Autodesk Fusion 360 part; units mm, degrees
(part 5 of 8)
sketch "D output shaft | protrusion from mounting face | profile (4)" plane through (0, 0, 2) normal (0, 0, 1) x (1, 0, 0) in component "J4 | NEMA17 drawing reference"
  line L0 (-2.5, 0) -> (-2.4786, -0.3263)
  line L1 (-2.4786, -0.3263) -> (-2.4148, -0.647)
  line L2 (-2.4148, -0.647) -> (-2.3097, -0.9567)
  line L3 (-2.3097, -0.9567) -> (-2.1651, -1.25)
  line L4 (-2.1651, -1.25) -> (-1.9834, -1.5219)
  line L5 (-1.9834, -1.5219) -> (-1.7678, -1.7678)
  line L6 (-1.7678, -1.7678) -> (-1.5219, -1.9834)
  line L7 (-1.5219, -1.9834) -> (-1.25, -2.1651)
  line L8 (-1.25, -2.1651) -> (-0.9567, -2.3097)
  line L9 (-0.9567, -2.3097) -> (-0.647, -2.4148)
  line L10 (-0.647, -2.4148) -> (-0.3263, -2.4786)
  line L11 (-0.3263, -2.4786) -> (0, -2.5)
  line L12 (0, -2.5) -> (0.3263, -2.4786)
  line L13 (0.3263, -2.4786) -> (0.647, -2.4148)
  line L14 (0.647, -2.4148) -> (0.9567, -2.3097)
  line L15 (0.9567, -2.3097) -> (1.25, -2.1651)
  line L16 (1.25, -2.1651) -> (1.5219, -1.9834)
  line L17 (1.5219, -1.9834) -> (1.7678, -1.7678)
  line L18 (1.7678, -1.7678) -> (1.9834, -1.5219)
  line L19 (1.9834, -1.5219) -> (2, -1.25)
  line L20 (2, -1.25) -> (2, 1.25)
  line L21 (2, 1.25) -> (1.9834, 1.5219)
  line L22 (1.9834, 1.5219) -> (1.7678, 1.7678)
  line L23 (1.7678, 1.7678) -> (1.5219, 1.9834)
  line L24 (1.5219, 1.9834) -> (1.25, 2.1651)
  line L25 (1.25, 2.1651) -> (0.9567, 2.3097)
  line L26 (0.9567, 2.3097) -> (0.647, 2.4148)
  line L27 (0.647, 2.4148) -> (0.3263, 2.4786)
  line L28 (0.3263, 2.4786) -> (0, 2.5)
  line L29 (0, 2.5) -> (-0.3263, 2.4786)
  line L30 (-0.3263, 2.4786) -> (-0.647, 2.4148)
  line L31 (-0.647, 2.4148) -> (-0.9567, 2.3097)
  line L32 (-0.9567, 2.3097) -> (-1.25, 2.1651)
  line L33 (-1.25, 2.1651) -> (-1.5219, 1.9834)
  line L34 (-1.5219, 1.9834) -> (-1.7678, 1.7678)
  line L35 (-1.7678, 1.7678) -> (-1.9834, 1.5219)
  line L36 (-1.9834, 1.5219) -> (-2.1651, 1.25)
  line L37 (-2.1651, 1.25) -> (-2.3097, 0.9567)
  line L38 (-2.3097, 0.9567) -> (-2.4148, 0.647)
  line L39 (-2.4148, 0.647) -> (-2.4786, 0.3263)
  line L40 (-2.4786, 0.3263) -> (-2.5, 0)
extrude "D output shaft | protrusion from mounting face'''" add sketch "D output shaft | protrusion from mounting face | profile (4)" along normal blind 21 separate body makes body 193 in component "J4 | NEMA17 drawing reference"
ref_plane "WorkPlane5" through (0, 0, -39) normal (0, 0, 1) x (1, 0, 0) in component "J4 | NEMA17 drawing reference"
sketch "Cable connector | profile (4)" plane through (0, 0, -39) normal (0, 0, 1) x (1, 0, 0) in component "J4 | NEMA17 drawing reference"
  line L0 (-5.2, -24.65) -> (5.2, -24.65)
  line L1 (5.2, -24.65) -> (6, -23.85)
  line L2 (6, -23.85) -> (6, -20.45)
  line L3 (6, -20.45) -> (5.2, -19.65)
  line L4 (5.2, -19.65) -> (-5.2, -19.65)
  line L5 (-5.2, -19.65) -> (-6, -20.45)
  line L6 (-6, -20.45) -> (-6, -23.85)
  line L7 (-6, -23.85) -> (-5.2, -24.65)
extrude "Cable connector'''" add sketch "Cable connector | profile (4)" along normal blind 8 separate body makes body 194 in component "J4 | NEMA17 drawing reference"
sketch "MG996R case | 40.7 x 19.7 x 37 nominal | profile" plane through (0, 0, 0) normal (0, 0, 1) x (1, 0, 0) in component "MG996R Robot 180 | drawing reconstruction, fit pending"
  line L0 (-19.35, -9.85) -> (19.35, -9.85)
  line L1 (19.35, -9.85) -> (20.35, -8.85)
  line L2 (20.35, -8.85) -> (20.35, 8.85)
  line L3 (20.35, 8.85) -> (19.35, 9.85)
  line L4 (19.35, 9.85) -> (-19.35, 9.85)
  line L5 (-19.35, 9.85) -> (-20.35, 8.85)
  line L6 (-20.35, 8.85) -> (-20.35, -8.85)
  line L7 (-20.35, -8.85) -> (-19.35, -9.85)
extrude "MG996R case | 40.7 x 19.7 x 37 nominal" add sketch "MG996R case | 40.7 x 19.7 x 37 nominal | profile" along normal blind 32 separate body makes body 195 in component "MG996R Robot 180 | drawing reconstruction, fit pending"
ref_plane "WorkPlane1" through (0, 0, 32) normal (0, 0, 1) x (1, 0, 0) in component "MG996R Robot 180 | drawing reconstruction, fit pending"
sketch "MG996R top cover | profile" plane through (0, 0, 32) normal (0, 0, 1) x (1, 0, 0) in component "MG996R Robot 180 | drawing reconstruction, fit pending"
  line L0 (-19.35, -9.85) -> (19.35, -9.85)
  line L1 (19.35, -9.85) -> (20.35, -8.85)
  line L2 (20.35, -8.85) -> (20.35, 8.85)
  line L3 (20.35, 8.85) -> (19.35, 9.85)
  line L4 (19.35, 9.85) -> (-19.35, 9.85)
  line L5 (-19.35, 9.85) -> (-20.35, 8.85)
  line L6 (-20.35, 8.85) -> (-20.35, -8.85)
  line L7 (-20.35, -8.85) -> (-19.35, -9.85)
extrude "MG996R top cover" add sketch "MG996R top cover | profile" along normal blind 5 separate body makes body 196 in component "MG996R Robot 180 | drawing reconstruction, fit pending"
ref_plane "WorkPlane2" through (0, 0, 37) normal (0, 0, 1) x (1, 0, 0) in component "MG996R Robot 180 | drawing reconstruction, fit pending"
sketch "MG996R boss | offset is provisional | profile" plane through (0, 0, 37) normal (0, 0, 1) x (1, 0, 0) in component "MG996R Robot 180 | drawing reconstruction, fit pending"
  circle A0 centre (10.35, 0) radius 6.5
extrude "MG996R boss | offset is provisional" add sketch "MG996R boss | offset is provisional | profile" along normal blind 2.5 separate body makes body 197 in component "MG996R Robot 180 | drawing reconstruction, fit pending"
ref_plane "WorkPlane3" through (0, 0, 39.5) normal (0, 0, 1) x (1, 0, 0) in component "MG996R Robot 180 | drawing reconstruction, fit pending"
sketch "MG996R spline envelope | purchased fit pending | profile" plane through (0, 0, 39.5) normal (0, 0, 1) x (1, 0, 0) in component "MG996R Robot 180 | drawing reconstruction, fit pending"
  circle A0 centre (10.35, 0) radius 3
extrude "MG996R spline envelope | purchased fit pending" add sketch "MG996R spline envelope | purchased fit pending | profile" along normal blind 3.4 separate body makes body 198 in component "MG996R Robot 180 | drawing reconstruction, fit pending"
ref_plane "WorkPlane4" through (0, 0, 26.8) normal (0, 0, 1) x (1, 0, 0) in component "MG996R Robot 180 | drawing reconstruction, fit pending"
sketch "MG996R nominal ear | verify hole pattern | profile" plane through (0, 0, 26.8) normal (0, 0, 1) x (1, 0, 0) in component "MG996R Robot 180 | drawing reconstruction, fit pending"
  line L0 (-26.4, -10) -> (-20.95, -10)
  line L1 (-20.95, -10) -> (-20.35, -9.4)
  line L2 (-20.35, -9.4) -> (-20.35, 9.4)
  line L3 (-20.35, 9.4) -> (-20.95, 10)
  line L4 (-20.95, 10) -> (-26.4, 10)
  line L5 (-26.4, 10) -> (-27, 9.4)
  line L6 (-27, 9.4) -> (-27, -9.4)
  line L7 (-27, -9.4) -> (-26.4, -10)
  circle A0 centre (-24.25, -5) radius 1.25
  circle A1 centre (-24.25, 5) radius 1.25
extrude "MG996R nominal ear | verify hole pattern" add sketch "MG996R nominal ear | verify hole pattern | profile" along normal blind 2.5 separate body makes body 199 in component "MG996R Robot 180 | drawing reconstruction, fit pending"
ref_plane "WorkPlane5" through (0, 0, 26.8) normal (0, 0, 1) x (1, 0, 0) in component "MG996R Robot 180 | drawing reconstruction, fit pending"
sketch "MG996R nominal ear | verify hole pattern | profile (1)" plane through (0, 0, 26.8) normal (0, 0, 1) x (1, 0, 0) in component "MG996R Robot 180 | drawing reconstruction, fit pending"
  line L0 (20.95, -10) -> (26.4, -10)
  line L1 (26.4, -10) -> (27, -9.4)
  line L2 (27, -9.4) -> (27, 9.4)
  line L3 (27, 9.4) -> (26.4, 10)
  line L4 (26.4, 10) -> (20.95, 10)
  line L5 (20.95, 10) -> (20.35, 9.4)
  line L6 (20.35, 9.4) -> (20.35, -9.4)
  line L7 (20.35, -9.4) -> (20.95, -10)
  circle A0 centre (24.25, -5) radius 1.25
  circle A1 centre (24.25, 5) radius 1.25
extrude "MG996R nominal ear | verify hole pattern (1)" add sketch "MG996R nominal ear | verify hole pattern | profile (1)" along normal blind 2.5 separate body makes body 200 in component "MG996R Robot 180 | drawing reconstruction, fit pending"
ref_plane "WorkPlane6" through (0, 0, 36.8) normal (0, 0, 1) x (1, 0, 0) in component "MG996R Robot 180 | drawing reconstruction, fit pending"
sketch "MG996R case screw | profile" plane through (0, 0, 36.8) normal (0, 0, 1) x (1, 0, 0) in component "MG996R Robot 180 | drawing reconstruction, fit pending"
  line L0 (-15.8742, -5.35) -> (-17, -4.7)
  line L1 (-17, -4.7) -> (-18.1258, -5.35)
  line L2 (-18.1258, -5.35) -> (-18.1258, -6.65)
  line L3 (-18.1258, -6.65) -> (-17, -7.3)
  line L4 (-17, -7.3) -> (-15.8742, -6.65)
  line L5 (-15.8742, -6.65) -> (-15.8742, -5.35)
  circle A0 centre (-17, -6) radius 0.9
extrude "MG996R case screw" add sketch "MG996R case screw | profile" along normal blind 1 separate body makes body 201 in component "MG996R Robot 180 | drawing reconstruction, fit pending"
ref_plane "WorkPlane7" through (0, 0, 36.8) normal (0, 0, 1) x (1, 0, 0) in component "MG996R Robot 180 | drawing reconstruction, fit pending"
sketch "MG996R case screw | profile (1)" plane through (0, 0, 36.8) normal (0, 0, 1) x (1, 0, 0) in component "MG996R Robot 180 | drawing reconstruction, fit pending"
  line L0 (-15.8742, 6.65) -> (-17, 7.3)
  line L1 (-17, 7.3) -> (-18.1258, 6.65)
  line L2 (-18.1258, 6.65) -> (-18.1258, 5.35)
  line L3 (-18.1258, 5.35) -> (-17, 4.7)
  line L4 (-17, 4.7) -> (-15.8742, 5.35)
  line L5 (-15.8742, 5.35) -> (-15.8742, 6.65)
  circle A0 centre (-17, 6) radius 0.9
extrude "MG996R case screw (1)" add sketch "MG996R case screw | profile (1)" along normal blind 1 separate body makes body 202 in component "MG996R Robot 180 | drawing reconstruction, fit pending"
ref_plane "WorkPlane8" through (0, 0, 36.8) normal (0, 0, 1) x (1, 0, 0) in component "MG996R Robot 180 | drawing reconstruction, fit pending"
sketch "MG996R case screw | profile (2)" plane through (0, 0, 36.8) normal (0, 0, 1) x (1, 0, 0) in component "MG996R Robot 180 | drawing reconstruction, fit pending"
  line L0 (18.1258, -5.35) -> (17, -4.7)
  line L1 (17, -4.7) -> (15.8742, -5.35)
  line L2 (15.8742, -5.35) -> (15.8742, -6.65)
  line L3 (15.8742, -6.65) -> (17, -7.3)
  line L4 (17, -7.3) -> (18.1258, -6.65)
  line L5 (18.1258, -6.65) -> (18.1258, -5.35)
  circle A0 centre (17, -6) radius 0.9
extrude "MG996R case screw (2)" add sketch "MG996R case screw | profile (2)" along normal blind 1 separate body makes body 203 in component "MG996R Robot 180 | drawing reconstruction, fit pending"
ref_plane "WorkPlane9" through (0, 0, 36.8) normal (0, 0, 1) x (1, 0, 0) in component "MG996R Robot 180 | drawing reconstruction, fit pending"
sketch "MG996R case screw | profile (3)" plane through (0, 0, 36.8) normal (0, 0, 1) x (1, 0, 0) in component "MG996R Robot 180 | drawing reconstruction, fit pending"
  line L0 (18.1258, 6.65) -> (17, 7.3)
  line L1 (17, 7.3) -> (15.8742, 6.65)
  line L2 (15.8742, 6.65) -> (15.8742, 5.35)
  line L3 (15.8742, 5.35) -> (17, 4.7)
  line L4 (17, 4.7) -> (18.1258, 5.35)
  line L5 (18.1258, 5.35) -> (18.1258, 6.65)
  circle A0 centre (17, 6) radius 0.9
extrude "MG996R case screw (3)" add sketch "MG996R case screw | profile (3)" along normal blind 1 separate body makes body 204 in component "MG996R Robot 180 | drawing reconstruction, fit pending"
ref_plane "WorkPlane1" through (0, 0, -14) normal (0, 0, 1) x (1, 0, 0) in component "11:1 twin-disc shoulder | original geometry"
sketch "Fixed ring | 12 roller stations | profile" plane through (0, 0, -14) normal (0, 0, 1) x (1, 0, 0) in component "11:1 twin-disc shoulder | original geometry"
  circle A0 centre (0, 0) radius 49
  circle A1 centre (0, 0) radius 45.4
extrude "Fixed ring | 12 roller stations" add sketch "Fixed ring | 12 roller stations | profile" along normal blind 28 separate body makes body 205 in component "11:1 twin-disc shoulder | original geometry"
ref_plane "WorkPlane2" through (0, 0, -17) normal (0, 0, 1) x (1, 0, 0) in component "11:1 twin-disc shoulder | original geometry"
sketch "Rear roller support | profile" plane through (0, 0, -17) normal (0, 0, 1) x (1, 0, 0) in component "11:1 twin-disc shoulder | original geometry"
  line L0 (49, 0) -> (48.7641, 4.8028)
  line L1 (48.7641, 4.8028) -> (48.0585, 9.5594)
  line L2 (48.0585, 9.5594) -> (46.8901, 14.2239)
  line L3 (46.8901, 14.2239) -> (45.2701, 18.7515)
  line L4 (45.2701, 18.7515) -> (43.2141, 23.0984)
  line L5 (43.2141, 23.0984) -> (40.742, 27.2229)
  line L6 (40.742, 27.2229) -> (37.8775, 31.0853)
  line L7 (37.8775, 31.0853) -> (34.6482, 34.6482)
  line L8 (34.6482, 34.6482) -> (31.0853, 37.8775)
  line L9 (31.0853, 37.8775) -> (27.2229, 40.742)
  line L10 (27.2229, 40.742) -> (23.0984, 43.2141)
  line L11 (23.0984, 43.2141) -> (18.7515, 45.2701)
  line L12 (18.7515, 45.2701) -> (14.2239, 46.8901)
  line L13 (14.2239, 46.8901) -> (9.5594, 48.0585)
  line L14 (9.5594, 48.0585) -> (4.8028, 48.7641)
  line L15 (4.8028, 48.7641) -> (0, 49)
  line L16 (0, 49) -> (-4.8028, 48.7641)
  line L17 (-4.8028, 48.7641) -> (-9.5594, 48.0585)
  line L18 (-9.5594, 48.0585) -> (-14.2239, 46.8901)
  line L19 (-14.2239, 46.8901) -> (-18.7515, 45.2701)
  line L20 (-18.7515, 45.2701) -> (-23.0984, 43.2141)
  line L21 (-23.0984, 43.2141) -> (-27.2229, 40.742)
  line L22 (-27.2229, 40.742) -> (-31.0853, 37.8775)
  line L23 (-31.0853, 37.8775) -> (-34.6482, 34.6482)
  line L24 (-34.6482, 34.6482) -> (-37.8775, 31.0853)
  line L25 (-37.8775, 31.0853) -> (-40.742, 27.2229)
  line L26 (-40.742, 27.2229) -> (-43.2141, 23.0984)
  line L27 (-43.2141, 23.0984) -> (-45.2701, 18.7515)
  line L28 (-45.2701, 18.7515) -> (-46.8901, 14.2239)
  line L29 (-46.8901, 14.2239) -> (-48.0585, 9.5594)
  line L30 (-48.0585, 9.5594) -> (-48.7641, 4.8028)
  line L31 (-48.7641, 4.8028) -> (-49, 0)
  line L32 (-49, 0) -> (-48.7641, -4.8028)
  line L33 (-48.7641, -4.8028) -> (-48.0585, -9.5594)
  line L34 (-48.0585, -9.5594) -> (-46.8901, -14.2239)
  line L35 (-46.8901, -14.2239) -> (-45.2701, -18.7515)
  line L36 (-45.2701, -18.7515) -> (-43.2141, -23.0984)
  line L37 (-43.2141, -23.0984) -> (-40.742, -27.2229)
  line L38 (-40.742, -27.2229) -> (-37.8775, -31.0853)
  line L39 (-37.8775, -31.0853) -> (-34.6482, -34.6482)
  line L40 (-34.6482, -34.6482) -> (-31.0853, -37.8775)
  line L41 (-31.0853, -37.8775) -> (-27.2229, -40.742)
  line L42 (-27.2229, -40.742) -> (-23.0984, -43.2141)
  line L43 (-23.0984, -43.2141) -> (-18.7515, -45.2701)
  line L44 (-18.7515, -45.2701) -> (-14.2239, -46.8901)
  line L45 (-14.2239, -46.8901) -> (-9.5594, -48.0585)
  line L46 (-9.5594, -48.0585) -> (-4.8028, -48.7641)
  line L47 (-4.8028, -48.7641) -> (0, -49)
  line L48 (0, -49) -> (4.8028, -48.7641)
  line L49 (4.8028, -48.7641) -> (9.5594, -48.0585)
  line L50 (9.5594, -48.0585) -> (14.2239, -46.8901)
  line L51 (14.2239, -46.8901) -> (18.7515, -45.2701)
  line L52 (18.7515, -45.2701) -> (23.0984, -43.2141)
  line L53 (23.0984, -43.2141) -> (27.2229, -40.742)
  line L54 (27.2229, -40.742) -> (31.0853, -37.8775)
  line L55 (31.0853, -37.8775) -> (34.6482, -34.6482)
  line L56 (34.6482, -34.6482) -> (37.8775, -31.0853)
  line L57 (37.8775, -31.0853) -> (40.742, -27.2229)
  line L58 (40.742, -27.2229) -> (43.2141, -23.0984)
  line L59 (43.2141, -23.0984) -> (45.2701, -18.7515)
  line L60 (45.2701, -18.7515) -> (46.8901, -14.2239)
  line L61 (46.8901, -14.2239) -> (48.0585, -9.5594)
  line L62 (48.0585, -9.5594) -> (48.7641, -4.8028)
  line L63 (48.7641, -4.8028) -> (49, 0)
  circle A0 centre (0, 0) radius 21.1
  circle A1 centre (47, 0) radius 1.6
  circle A2 centre (23.5, 40.7032) radius 1.6
  circle A3 centre (-23.5, 40.7032) radius 1.6
  circle A4 centre (-47, 0) radius 1.6
  circle A5 centre (-23.5, -40.7032) radius 1.6
  circle A6 centre (23.5, -40.7032) radius 1.6
extrude "Rear roller support" add sketch "Rear roller support | profile" along normal blind 3 separate body makes body 206 in component "11:1 twin-disc shoulder | original geometry"
ref_plane "WorkPlane3" through (0, 0, 14) normal (0, 0, 1) x (1, 0, 0) in component "11:1 twin-disc shoulder | original geometry"
sketch "Front roller support | profile" plane through (0, 0, 14) normal (0, 0, 1) x (1, 0, 0) in component "11:1 twin-disc shoulder | original geometry"
  line L0 (49, 0) -> (48.7641, 4.8028)
  line L1 (48.7641, 4.8028) -> (48.0585, 9.5594)
  line L2 (48.0585, 9.5594) -> (46.8901, 14.2239)
  line L3 (46.8901, 14.2239) -> (45.2701, 18.7515)
  line L4 (45.2701, 18.7515) -> (43.2141, 23.0984)
  line L5 (43.2141, 23.0984) -> (40.742, 27.2229)
  line L6 (40.742, 27.2229) -> (37.8775, 31.0853)
  line L7 (37.8775, 31.0853) -> (34.6482, 34.6482)
  line L8 (34.6482, 34.6482) -> (31.0853, 37.8775)
  line L9 (31.0853, 37.8775) -> (27.2229, 40.742)
  line L10 (27.2229, 40.742) -> (23.0984, 43.2141)
  line L11 (23.0984, 43.2141) -> (18.7515, 45.2701)
  line L12 (18.7515, 45.2701) -> (14.2239, 46.8901)
  line L13 (14.2239, 46.8901) -> (9.5594, 48.0585)
  line L14 (9.5594, 48.0585) -> (4.8028, 48.7641)
  line L15 (4.8028, 48.7641) -> (0, 49)
  line L16 (0, 49) -> (-4.8028, 48.7641)
  line L17 (-4.8028, 48.7641) -> (-9.5594, 48.0585)
  line L18 (-9.5594, 48.0585) -> (-14.2239, 46.8901)
  line L19 (-14.2239, 46.8901) -> (-18.7515, 45.2701)
  line L20 (-18.7515, 45.2701) -> (-23.0984, 43.2141)
  line L21 (-23.0984, 43.2141) -> (-27.2229, 40.742)
  line L22 (-27.2229, 40.742) -> (-31.0853, 37.8775)
  line L23 (-31.0853, 37.8775) -> (-34.6482, 34.6482)
  line L24 (-34.6482, 34.6482) -> (-37.8775, 31.0853)
  line L25 (-37.8775, 31.0853) -> (-40.742, 27.2229)
  line L26 (-40.742, 27.2229) -> (-43.2141, 23.0984)
  line L27 (-43.2141, 23.0984) -> (-45.2701, 18.7515)
  line L28 (-45.2701, 18.7515) -> (-46.8901, 14.2239)
  line L29 (-46.8901, 14.2239) -> (-48.0585, 9.5594)
  line L30 (-48.0585, 9.5594) -> (-48.7641, 4.8028)
  line L31 (-48.7641, 4.8028) -> (-49, 0)
  line L32 (-49, 0) -> (-48.7641, -4.8028)
  line L33 (-48.7641, -4.8028) -> (-48.0585, -9.5594)
  line L34 (-48.0585, -9.5594) -> (-46.8901, -14.2239)
  line L35 (-46.8901, -14.2239) -> (-45.2701, -18.7515)
  line L36 (-45.2701, -18.7515) -> (-43.2141, -23.0984)
  line L37 (-43.2141, -23.0984) -> (-40.742, -27.2229)
  line L38 (-40.742, -27.2229) -> (-37.8775, -31.0853)
  line L39 (-37.8775, -31.0853) -> (-34.6482, -34.6482)
  line L40 (-34.6482, -34.6482) -> (-31.0853, -37.8775)
  line L41 (-31.0853, -37.8775) -> (-27.2229, -40.742)
  line L42 (-27.2229, -40.742) -> (-23.0984, -43.2141)
  line L43 (-23.0984, -43.2141) -> (-18.7515, -45.2701)
  line L44 (-18.7515, -45.2701) -> (-14.2239, -46.8901)
  line L45 (-14.2239, -46.8901) -> (-9.5594, -48.0585)
  line L46 (-9.5594, -48.0585) -> (-4.8028, -48.7641)
  line L47 (-4.8028, -48.7641) -> (0, -49)
  line L48 (0, -49) -> (4.8028, -48.7641)
  line L49 (4.8028, -48.7641) -> (9.5594, -48.0585)
  line L50 (9.5594, -48.0585) -> (14.2239, -46.8901)
  line L51 (14.2239, -46.8901) -> (18.7515, -45.2701)
  line L52 (18.7515, -45.2701) -> (23.0984, -43.2141)
  line L53 (23.0984, -43.2141) -> (27.2229, -40.742)
  line L54 (27.2229, -40.742) -> (31.0853, -37.8775)
  line L55 (31.0853, -37.8775) -> (34.6482, -34.6482)
  line L56 (34.6482, -34.6482) -> (37.8775, -31.0853)
  line L57 (37.8775, -31.0853) -> (40.742, -27.2229)
  line L58 (40.742, -27.2229) -> (43.2141, -23.0984)
  line L59 (43.2141, -23.0984) -> (45.2701, -18.7515)
  line L60 (45.2701, -18.7515) -> (46.8901, -14.2239)
  line L61 (46.8901, -14.2239) -> (48.0585, -9.5594)
  line L62 (48.0585, -9.5594) -> (48.7641, -4.8028)
  line L63 (48.7641, -4.8028) -> (49, 0)
  circle A0 centre (0, 0) radius 21.1
  circle A1 centre (47, 0) radius 1.6
  circle A2 centre (23.5, 40.7032) radius 1.6
  circle A3 centre (-23.5, 40.7032) radius 1.6
  circle A4 centre (-47, 0) radius 1.6
  circle A5 centre (-23.5, -40.7032) radius 1.6
  circle A6 centre (23.5, -40.7032) radius 1.6
extrude "Front roller support" add sketch "Front roller support | profile" along normal blind 3 separate body makes body 207 in component "11:1 twin-disc shoulder | original geometry"
ref_plane "WorkPlane4" through (0, 0, -6) normal (0, 0, 1) x (1, 0, 0) in component "11:1 twin-disc shoulder | original geometry"
sketch "Cycloidal disc A | 11 lobes | profile" plane through (0, 0, -6) normal (0, 0, 1) x (1, 0, 0) in component "11:1 twin-disc shoulder | original geometry"
  spline S0 degree 3 poles (34.9, 0) (34.9, 0.4967) (35.0026, 1.49) (35.3283, 2.6754) (35.659, 3.5694) (35.9489, 4.2967) (36.1986, 4.9569) (36.4118, 5.6126) (36.5843, 6.2979) (36.7055, 7.0274) (36.7619, 7.8014) (36.7413, 8.61) (36.635, 9.4363) (36.4398, 10.2593) (36.159, 11.0571) (35.8018, 11.8097) (35.382, 12.501) (34.916, 13.1217) (34.4197, 13.6699) (33.9041, 14.1531) (33.3703, 14.5895) (32.8032, 15.0099) (32.1662, 15.465) (31.4046, 16.0383) (30.4898, 16.8594) (29.5547, 18.0297) (28.8787, 19.3664) (28.5118, 20.5396) (28.3067, 21.4705) (28.1573, 22.2391) (28.0104, 22.9295) (27.8353, 23.5964) (27.6099, 24.2662) (27.3174, 24.9453) (26.9464, 25.627) (26.4919, 26.2961) (25.9558, 26.9337) (25.3467, 27.5205) (24.6791, 28.0399) (23.9717, 28.4799) (23.2448, 28.8345) (22.5172, 29.1047) (21.8033, 29.2975) (21.1083, 29.4253) (20.4233, 29.5038) (19.719, 29.5509) (18.937, 29.5894) (17.9864, 29.6599) (16.7728, 29.8561) (15.3535, 30.335) (14.0622, 31.094) (13.1192, 31.8827) (12.4433, 32.5549) (11.9022, 33.1207) (11.4054, 33.6222) (10.8975, 34.0885) (10.3457, 34.5301) (9.7325, 34.9433) (9.0519, 35.3162) (8.3078, 35.6333) (7.5121, 35.8798) (6.6824, 36.0442) (5.84, 36.1203) (5.007, 36.1079) (4.2037, 36.0133) (3.4456, 35.8472) (2.7408, 35.6235) (2.087, 35.3552) (1.4683, 35.0509) (0.8503, 34.7098) (0.1717, 34.3193) (-0.6661, 33.8647) (-1.7931, 33.3737) (-3.246, 33.0092) (-4.7428, 32.9496) (-5.9624, 33.1032) (-6.8944, 33.3034) (-7.6555, 33.4868) (-8.3446, 33.64) (-9.0239, 33.7577) (-9.7268, 33.8309) (-10.4662, 33.847) (-11.2403, 33.7927) (-12.0377, 33.6573) (-12.8404, 33.4344) (-13.6273, 33.1241) (-14.3771, 32.7327) (-15.0711, 32.272) (-15.6957, 31.758) (-16.2437, 31.2085) (-16.7157, 30.6392) (-17.1206, 30.0601) (-17.4766, 29.4696) (-17.812, 28.8485) (-18.1718, 28.1531) (-18.6309, 27.3177) (-19.3135, 26.2954) (-20.3387, 25.2032) (-21.5656, 24.3439) (-22.6747, 23.8137) (-23.567, 23.4782) (-24.3064, 23.221) (-24.969, 22.9774) (-25.6041, 22.7091) (-26.235, 22.3907) (-26.8656, 22.0045) (-27.4876, 21.5403) (-28.0852, 20.9952) (-28.64, 20.3738) (-29.1341, 19.6874) (-29.5532, 18.9527) (-29.888, 18.1899) (-30.1356, 17.4198) (-30.2995, 16.6613) (-30.3888, 15.9272) (-30.4164, 15.221) (-30.3966, 14.5319) (-30.343, 13.828) (-30.2697, 13.0485) (-30.2043, 12.0975) (-30.2258, 10.8684) (-30.4978, 9.3954) (-31.0653, 8.0091) (-31.7117, 6.9635) (-32.281, 6.1989) (-32.764, 5.5828) (-33.1896, 5.0196) (-33.5789, 4.4505) (-33.9375, 3.8416) (-34.2592, 3.1758) (-34.5315, 2.449) (-34.7395, 1.6674) (-34.8702, 0.8446) (-34.9149, 0) (-34.8702, -0.8446) (-34.7395, -1.6674) (-34.5315, -2.449) (-34.2592, -3.1758) (-33.9375, -3.8416) (-33.5789, -4.4505) (-33.1896, -5.0196) (-32.764, -5.5828) (-32.281, -6.1989) (-31.7117, -6.9635) (-31.0653, -8.0091) (-30.4978, -9.3954) (-30.2258, -10.8684) (-30.2043, -12.0975) (-30.2697, -13.0485) (-30.343, -13.828) (-30.3966, -14.5319) (-30.4164, -15.221) (-30.3888, -15.9272) (-30.2995, -16.6613) (-30.1356, -17.4198) (-29.888, -18.1899) (-29.5532, -18.9527) (-29.1341, -19.6874) (-28.64, -20.3738) (-28.0852, -20.9952) (-27.4876, -21.5403) (-26.8656, -22.0045) (-26.235, -22.3907) (-25.6041, -22.7091) (-24.969, -22.9774) (-24.3064, -23.221) (-23.567, -23.4782) (-22.6747, -23.8137) (-21.5656, -24.3439) (-20.3387, -25.2032) (-19.3135, -26.2954) (-18.6309, -27.3177) (-18.1718, -28.1531) (-17.812, -28.8485) (-17.4766, -29.4696) (-17.1206, -30.0601) (-16.7157, -30.6392) (-16.2437, -31.2085) (-15.6957, -31.758) (-15.0711, -32.272) (-14.3771, -32.7327) (-13.6273, -33.1241) (-12.8404, -33.4344) (-12.0377, -33.6573) (-11.2403, -33.7927) (-10.4662, -33.847) (-9.7268, -33.8309) (-9.0239, -33.7577) (-8.3446, -33.64) (-7.6555, -33.4868) (-6.8944, -33.3034) (-5.9624, -33.1032) (-4.7428, -32.9496) (-3.246, -33.0092) (-1.7931, -33.3737) (-0.6661, -33.8647) (0.1717, -34.3193) (0.8503, -34.7098) (1.4683, -35.0509) (2.087, -35.3552) (2.7408, -35.6235) (3.4456, -35.8472) (4.2037, -36.0133) (5.007, -36.1079) (5.84, -36.1203) (6.6824, -36.0442) (7.5121, -35.8798) (8.3078, -35.6333) (9.0519, -35.3162) (9.7325, -34.9433) (10.3457, -34.5301) (10.8975, -34.0885) (11.4054, -33.6222) (11.9022, -33.1207) (12.4433, -32.5549) (13.1192, -31.8827) (14.0622, -31.094) (15.3535, -30.335) (16.7728, -29.8561) (17.9864, -29.6599) (18.937, -29.5894) (19.719, -29.5509) (20.4233, -29.5038) (21.1083, -29.4253) (21.8033, -29.2975) (22.5172, -29.1047) (23.2448, -28.8345) (23.9717, -28.4799) (24.6791, -28.0399) (25.3467, -27.5205) (25.9558, -26.9337) (26.4919, -26.2961) (26.9464, -25.627) (27.3174, -24.9453) (27.6099, -24.2662) (27.8353, -23.5964) (28.0104, -22.9295) (28.1573, -22.2391) (28.3067, -21.4705) (28.5118, -20.5396) (28.8787, -19.3664) (29.5547, -18.0297) (30.4898, -16.8594) (31.4046, -16.0383) (32.1662, -15.465) (32.8032, -15.0099) (33.3703, -14.5895) (33.9041, -14.1531) (34.4197, -13.6699) (34.916, -13.1217) (35.382, -12.501) (35.8018, -11.8097) (36.159, -11.0571) (36.4398, -10.2593) (36.635, -9.4363) (36.7413, -8.61) (36.7619, -7.8014) (36.7055, -7.0274) (36.5843, -6.2979) (36.4118, -5.6126) (36.1986, -4.9569) (35.9489, -4.2967) (35.659, -3.5694) (35.3283, -2.6754) (35.0026, -1.49) (34.9, -0.4967) (34.9, 0) knots 3 3 3 3 4 5 6 7 8 9 10 11 12 13 14 15 16 17 18 19 20 21 22 23 24 25 26 27 28 29 30 31 32 33 34 35 36 37 38 39 40 41 42 43 44 45 46 47 48 49 50 51 52 53 54 55 56 57 58 59 60 61 62 63 64 65 66 67 68 69 70 71 72 73 74 75 76 77 78 79 80 81 82 83 84 85 86 87 88 89 90 91 92 93 94 95 96 97 98 99 100 101 102 103 104 105 106 107 108 109 110 111 112 113 114 115 116 117 118 119 120 121 122 123 124 125 126 127 128 129 130 131 132 133 134 135 136 137 138 139 140 141 142 143 144 145 146 147 148 149 150 151 152 153 154 155 156 157 158 159 160 161 162 163 164 165 166 167 168 169 170 171 172 173 174 175 176 177 178 179 180 181 182 183 184 185 186 187 188 189 190 191 192 193 194 195 196 197 198 199 200 201 202 203 204 205 206 207 208 209 210 211 212 213 214 215 216 217 218 219 220 221 222 223 224 225 226 227 228 229 230 231 232 233 234 235 236 237 238 239 240 241 242 243 244 245 246 247 248 249 250 251 252 253 254 255 256 257 258 259 260 261 262 263 264 265 266 267 267 267 267
  circle A0 centre (1.5, 0) radius 10.6
  circle A1 centre (23.5, 0) radius 3.65
  circle A2 centre (12.5, 19.0526) radius 3.65
  circle A3 centre (-9.5, 19.0526) radius 3.65
  circle A4 centre (-20.5, 0) radius 3.65
  circle A5 centre (-9.5, -19.0526) radius 3.65
  circle A6 centre (12.5, -19.0526) radius 3.65
extrude "Cycloidal disc A | 11 lobes" add sketch "Cycloidal disc A | 11 lobes | profile" along normal blind 5 separate body makes body 208 in component "11:1 twin-disc shoulder | original geometry"
ref_plane "WorkPlane5" through (0, 0, -6) normal (0, 0, 1) x (1, 0, 0) in component "11:1 twin-disc shoulder | original geometry"
sketch "Eccentric bearing A outer race | profile" plane through (0, 0, -6) normal (0, 0, 1) x (1, 0, 0) in component "11:1 twin-disc shoulder | original geometry"
  circle A0 centre (1.5, 0) radius 10.5
  circle A1 centre (1.5, 0) radius 9.5
extrude "Eccentric bearing A outer race" add sketch "Eccentric bearing A outer race | profile" along normal blind 5 separate body makes body 209 in component "11:1 twin-disc shoulder | original geometry"
ref_plane "WorkPlane6" through (0, 0, -6) normal (0, 0, 1) x (1, 0, 0) in component "11:1 twin-disc shoulder | original geometry"
sketch "Eccentric bearing A inner race | profile" plane through (0, 0, -6) normal (0, 0, 1) x (1, 0, 0) in component "11:1 twin-disc shoulder | original geometry"
  circle A0 centre (1.5, 0) radius 7
  circle A1 centre (1.5, 0) radius 6
extrude "Eccentric bearing A inner race" add sketch "Eccentric bearing A inner race | profile" along normal blind 5 separate body makes body 210 in component "11:1 twin-disc shoulder | original geometry"
ref_plane "WorkPlane7" through (0, 0, -5.85) normal (0, 0, 1) x (1, 0, 0) in component "11:1 twin-disc shoulder | original geometry"
sketch "Eccentric bearing A shield | profile" plane through (0, 0, -5.85) normal (0, 0, 1) x (1, 0, 0) in component "11:1 twin-disc shoulder | original geometry"
  circle A0 centre (1.5, 0) radius 9.5
  circle A1 centre (1.5, 0) radius 7
extrude "Eccentric bearing A shield" add sketch "Eccentric bearing A shield | profile" along normal blind 4.7 separate body makes body 211 in component "11:1 twin-disc shoulder | original geometry"
ref_plane "WorkPlane8" through (0, 0, -6) normal (0, 0, 1) x (1, 0, 0) in component "11:1 twin-disc shoulder | original geometry"
sketch "Steel eccentric cam A | profile" plane through (0, 0, -6) normal (0, 0, 1) x (1, 0, 0) in component "11:1 twin-disc shoulder | original geometry"
  circle A0 centre (1.5, 0) radius 6
  circle A1 centre (1.5, 0) radius 3
extrude "Steel eccentric cam A" add sketch "Steel eccentric cam A | profile" along normal blind 5 separate body makes body 212 in component "11:1 twin-disc shoulder | original geometry"
ref_plane "WorkPlane9" through (0, 0, 1) normal (0, 0, 1) x (1, 0, 0) in component "11:1 twin-disc shoulder | original geometry"
sketch "Cycloidal disc B | 11 lobes | profile" plane through (0, 0, 1) normal (0, 0, 1) x (1, 0, 0) in component "11:1 twin-disc shoulder | original geometry"
  spline S0 degree 3 poles (30.5471, -9.4099) (30.687, -8.9333) (31.0653, -8.0091) (31.7117, -6.9635) (32.281, -6.1989) (32.764, -5.5828) (33.1896, -5.0196) (33.5789, -4.4505) (33.9375, -3.8416) (34.2592, -3.1758) (34.5315, -2.449) (34.7395, -1.6674) (34.8702, -0.8446) (34.9149, 0) (34.8702, 0.8446) (34.7395, 1.6674) (34.5315, 2.449) (34.2592, 3.1758) (33.9375, 3.8416) (33.5789, 4.4505) (33.1896, 5.0196) (32.764, 5.5828) (32.281, 6.1989) (31.7117, 6.9635) (31.0653, 8.0091) (30.4978, 9.3954) (30.2258, 10.8684) (30.2043, 12.0975) (30.2697, 13.0485) (30.343, 13.828) (30.3966, 14.5319) (30.4164, 15.221) (30.3888, 15.9272) (30.2995, 16.6613) (30.1356, 17.4198) (29.888, 18.1899) (29.5532, 18.9527) (29.1341, 19.6874) (28.64, 20.3738) (28.0852, 20.9952) (27.4876, 21.5403) (26.8656, 22.0045) (26.235, 22.3907) (25.6041, 22.7091) (24.969, 22.9774) (24.3064, 23.221) (23.567, 23.4782) (22.6747, 23.8137) (21.5656, 24.3439) (20.3387, 25.2032) (19.3135, 26.2954) (18.6309, 27.3177) (18.1718, 28.1531) (17.812, 28.8485) (17.4766, 29.4696) (17.1206, 30.0601) (16.7157, 30.6392) (16.2437, 31.2085) (15.6957, 31.758) (15.0711, 32.272) (14.3771, 32.7327) (13.6273, 33.1241) (12.8404, 33.4344) (12.0377, 33.6573) (11.2403, 33.7927) (10.4662, 33.847) (9.7268, 33.8309) (9.0239, 33.7577) (8.3446, 33.64) (7.6555, 33.4868) (6.8944, 33.3034) (5.9624, 33.1032) (4.7428, 32.9496) (3.246, 33.0092) (1.7931, 33.3737) (0.6661, 33.8647) (-0.1717, 34.3193) (-0.8503, 34.7098) (-1.4683, 35.0509) (-2.087, 35.3552) (-2.7408, 35.6235) (-3.4456, 35.8472) (-4.2037, 36.0133) (-5.007, 36.1079) (-5.84, 36.1203) (-6.6824, 36.0442) (-7.5121, 35.8798) (-8.3078, 35.6333) (-9.0519, 35.3162) (-9.7325, 34.9433) (-10.3457, 34.5301) (-10.8975, 34.0885) (-11.4054, 33.6222) (-11.9022, 33.1207) (-12.4433, 32.5549) (-13.1192, 31.8827) (-14.0622, 31.094) (-15.3535, 30.335) (-16.7728, 29.8561) (-17.9864, 29.6599) (-18.937, 29.5894) (-19.719, 29.5509) (-20.4233, 29.5038) (-21.1083, 29.4253) (-21.8033, 29.2975) (-22.5172, 29.1047) (-23.2448, 28.8345) (-23.9717, 28.4799) (-24.6791, 28.0399) (-25.3467, 27.5205) (-25.9558, 26.9337) (-26.4919, 26.2961) (-26.9464, 25.627) (-27.3174, 24.9453) (-27.6099, 24.2662) (-27.8353, 23.5964) (-28.0104, 22.9295) (-28.1573, 22.2391) (-28.3067, 21.4705) (-28.5118, 20.5396) (-28.8787, 19.3664) (-29.5547, 18.0297) (-30.4898, 16.8594) (-31.4046, 16.0383) (-32.1662, 15.465) (-32.8032, 15.0099) (-33.3703, 14.5895) (-33.9041, 14.1531) (-34.4197, 13.6699) (-34.916, 13.1217) (-35.382, 12.501) (-35.8018, 11.8097) (-36.159, 11.0571) (-36.4398, 10.2593) (-36.635, 9.4363) (-36.7413, 8.61) (-36.7619, 7.8014) (-36.7055, 7.0274) (-36.5843, 6.2979) (-36.4118, 5.6126) (-36.1986, 4.9569) (-35.9489, 4.2967) (-35.659, 3.5694) (-35.3283, 2.6754) (-35.0026, 1.49) (-34.8487, 0) (-35.0026, -1.49) (-35.3283, -2.6754) (-35.659, -3.5694) (-35.9489, -4.2967) (-36.1986, -4.9569) (-36.4118, -5.6126) (-36.5843, -6.2979) (-36.7055, -7.0274) (-36.7619, -7.8014) (-36.7413, -8.61) (-36.635, -9.4363) (-36.4398, -10.2593) (-36.159, -11.0571) (-35.8018, -11.8097) (-35.382, -12.501) (-34.916, -13.1217) (-34.4197, -13.6699) (-33.9041, -14.1531) (-33.3703, -14.5895) (-32.8032, -15.0099) (-32.1662, -15.465) (-31.4046, -16.0383) (-30.4898, -16.8594) (-29.5547, -18.0297) (-28.8787, -19.3664) (-28.5118, -20.5396) (-28.3067, -21.4705) (-28.1573, -22.2391) (-28.0104, -22.9295) (-27.8353, -23.5964) (-27.6099, -24.2662) (-27.3174, -24.9453) (-26.9464, -25.627) (-26.4919, -26.2961) (-25.9558, -26.9337) (-25.3467, -27.5205) (-24.6791, -28.0399) (-23.9717, -28.4799) (-23.2448, -28.8345) (-22.5172, -29.1047) (-21.8033, -29.2975) (-21.1083, -29.4253) (-20.4233, -29.5038) (-19.719, -29.5509) (-18.937, -29.5894) (-17.9864, -29.6599) (-16.7728, -29.8561) (-15.3535, -30.335) (-14.0622, -31.094) (-13.1192, -31.8827) (-12.4433, -32.5549) (-11.9022, -33.1207) (-11.4054, -33.6222) (-10.8975, -34.0885) (-10.3457, -34.5301) (-9.7325, -34.9433) (-9.0519, -35.3162) (-8.3078, -35.6333) (-7.5121, -35.8798) (-6.6824, -36.0442) (-5.84, -36.1203) (-5.007, -36.1079) (-4.2037, -36.0133) (-3.4456, -35.8472) (-2.7408, -35.6235) (-2.087, -35.3552) (-1.4683, -35.0509) (-0.8503, -34.7098) (-0.1717, -34.3193) (0.6661, -33.8647) (1.7931, -33.3737) (3.246, -33.0092) (4.7428, -32.9496) (5.9624, -33.1032) (6.8944, -33.3034) (7.6555, -33.4868) (8.3446, -33.64) (9.0239, -33.7577) (9.7268, -33.8309) (10.4662, -33.847) (11.2403, -33.7927) (12.0377, -33.6573) (12.8404, -33.4344) (13.6273, -33.1241) (14.3771, -32.7327) (15.0711, -32.272) (15.6957, -31.758) (16.2437, -31.2085) (16.7157, -30.6392) (17.1206, -30.0601) (17.4766, -29.4696) (17.812, -28.8485) (18.1718, -28.1531) (18.6309, -27.3177) (19.3135, -26.2954) (20.3387, -25.2032) (21.5656, -24.3439) (22.6747, -23.8137) (23.567, -23.4782) (24.3064, -23.221) (24.969, -22.9774) (25.6041, -22.7091) (26.235, -22.3907) (26.8656, -22.0045) (27.4876, -21.5403) (28.0852, -20.9952) (28.64, -20.3738) (29.1341, -19.6874) (29.5532, -18.9527) (29.888, -18.1899) (30.1356, -17.4198) (30.2995, -16.6613) (30.3888, -15.9272) (30.4164, -15.221) (30.3966, -14.5319) (30.343, -13.828) (30.2697, -13.0485) (30.2043, -12.0975) (30.2258, -10.8684) (30.4071, -9.8864) (30.5471, -9.4099) knots 3 3 3 3 4 5 6 7 8 9 10 11 12 13 14 15 16 17 18 19 20 21 22 23 24 25 26 27 28 29 30 31 32 33 34 35 36 37 38 39 40 41 42 43 44 45 46 47 48 49 50 51 52 53 54 55 56 57 58 59 60 61 62 63 64 65 66 67 68 69 70 71 72 73 74 75 76 77 78 79 80 81 82 83 84 85 86 87 88 89 90 91 92 93 94 95 96 97 98 99 100 101 102 103 104 105 106 107 108 109 110 111 112 113 114 115 116 117 118 119 120 121 122 123 124 125 126 127 128 129 130 131 132 133 134 135 136 137 138 139 140 141 142 143 144 145 146 147 148 149 150 151 152 153 154 155 156 157 158 159 160 161 162 163 164 165 166 167 168 169 170 171 172 173 174 175 176 177 178 179 180 181 182 183 184 185 186 187 188 189 190 191 192 193 194 195 196 197 198 199 200 201 202 203 204 205 206 207 208 209 210 211 212 213 214 215 216 217 218 219 220 221 222 223 224 225 226 227 228 229 230 231 232 233 234 235 236 237 238 239 240 241 242 243 244 245 246 247 248 249 250 251 252 253 254 255 256 257 258 259 260 261 262 263 264 265 266 267 267 267 267
  circle A0 centre (-1.5, 0) radius 10.6
  circle A1 centre (20.5, 0) radius 3.65
  circle A2 centre (9.5, 19.0526) radius 3.65
  circle A3 centre (-12.5, 19.0526) radius 3.65
  circle A4 centre (-23.5, 0) radius 3.65
  circle A5 centre (-12.5, -19.0526) radius 3.65
  circle A6 centre (9.5, -19.0526) radius 3.65
extrude "Cycloidal disc B | 11 lobes" add sketch "Cycloidal disc B | 11 lobes | profile" along normal blind 5 separate body makes body 213 in component "11:1 twin-disc shoulder | original geometry"
ref_plane "WorkPlane10" through (0, 0, 1) normal (0, 0, 1) x (1, 0, 0) in component "11:1 twin-disc shoulder | original geometry"
sketch "Eccentric bearing B outer race | profile" plane through (0, 0, 1) normal (0, 0, 1) x (1, 0, 0) in component "11:1 twin-disc shoulder | original geometry"
  circle A0 centre (-1.5, 0) radius 10.5
  circle A1 centre (-1.5, 0) radius 9.5
extrude "Eccentric bearing B outer race" add sketch "Eccentric bearing B outer race | profile" along normal blind 5 separate body makes body 214 in component "11:1 twin-disc shoulder | original geometry"
ref_plane "WorkPlane11" through (0, 0, 1) normal (0, 0, 1) x (1, 0, 0) in component "11:1 twin-disc shoulder | original geometry"
sketch "Eccentric bearing B inner race | profile" plane through (0, 0, 1) normal (0, 0, 1) x (1, 0, 0) in component "11:1 twin-disc shoulder | original geometry"
  circle A0 centre (-1.5, 0) radius 7
  circle A1 centre (-1.5, 0) radius 6
extrude "Eccentric bearing B inner race" add sketch "Eccentric bearing B inner race | profile" along normal blind 5 separate body makes body 215 in component "11:1 twin-disc shoulder | original geometry"
ref_plane "WorkPlane12" through (0, 0, 1.15) normal (0, 0, 1) x (1, 0, 0) in component "11:1 twin-disc shoulder | original geometry"
sketch "Eccentric bearing B shield | profile" plane through (0, 0, 1.15) normal (0, 0, 1) x (1, 0, 0) in component "11:1 twin-disc shoulder | original geometry"
  circle A0 centre (-1.5, 0) radius 9.5
  circle A1 centre (-1.5, 0) radius 7
extrude "Eccentric bearing B shield" add sketch "Eccentric bearing B shield | profile" along normal blind 4.7 separate body makes body 216 in component "11:1 twin-disc shoulder | original geometry"
ref_plane "WorkPlane13" through (0, 0, 1) normal (0, 0, 1) x (1, 0, 0) in component "11:1 twin-disc shoulder | original geometry"
sketch "Steel eccentric cam B | profile" plane through (0, 0, 1) normal (0, 0, 1) x (1, 0, 0) in component "11:1 twin-disc shoulder | original geometry"
  circle A0 centre (-1.5, 0) radius 6
  circle A1 centre (-1.5, 0) radius 3
extrude "Steel eccentric cam B" add sketch "Steel eccentric cam B | profile" along normal blind 5 separate body makes body 217 in component "11:1 twin-disc shoulder | original geometry"
ref_plane "WorkPlane14" through (0, 0, -17) normal (0, 0, 1) x (1, 0, 0) in component "11:1 twin-disc shoulder | original geometry"
sketch "Fixed metal roller pin 1 | profile" plane through (0, 0, -17) normal (0, 0, 1) x (1, 0, 0) in component "11:1 twin-disc shoulder | original geometry"
  circle A0 centre (40, 0) radius 1.5
extrude "Fixed metal roller pin 1" add sketch "Fixed metal roller pin 1 | profile" along normal blind 34 separate body makes body 218 in component "11:1 twin-disc shoulder | original geometry"
ref_plane "WorkPlane15" through (0, 0, -6) normal (0, 0, 1) x (1, 0, 0) in component "11:1 twin-disc shoulder | original geometry"
sketch "623ZZ outer race | profile" plane through (0, 0, -6) normal (0, 0, 1) x (1, 0, 0) in component "11:1 twin-disc shoulder | original geometry"
  circle A0 centre (40, 0) radius 5
  circle A1 centre (40, 0) radius 4
extrude "623ZZ outer race" add sketch "623ZZ outer race | profile" along normal blind 4 separate body makes body 219 in component "11:1 twin-disc shoulder | original geometry"
ref_plane "WorkPlane16" through (0, 0, -6) normal (0, 0, 1) x (1, 0, 0) in component "11:1 twin-disc shoulder | original geometry"
sketch "623ZZ inner race | profile" plane through (0, 0, -6) normal (0, 0, 1) x (1, 0, 0) in component "11:1 twin-disc shoulder | original geometry"
  circle A0 centre (40, 0) radius 2.5
  circle A1 centre (40, 0) radius 1.5
extrude "623ZZ inner race" add sketch "623ZZ inner race | profile" along normal blind 4 separate body makes body 220 in component "11:1 twin-disc shoulder | original geometry"
ref_plane "WorkPlane17" through (0, 0, -5.85) normal (0, 0, 1) x (1, 0, 0) in component "11:1 twin-disc shoulder | original geometry"
sketch "623ZZ shield | profile" plane through (0, 0, -5.85) normal (0, 0, 1) x (1, 0, 0) in component "11:1 twin-disc shoulder | original geometry"
  circle A0 centre (40, 0) radius 4
  circle A1 centre (40, 0) radius 2.5
extrude "623ZZ shield" add sketch "623ZZ shield | profile" along normal blind 3.7 separate body makes body 221 in component "11:1 twin-disc shoulder | original geometry"
ref_plane "WorkPlane18" through (0, 0, 2) normal (0, 0, 1) x (1, 0, 0) in component "11:1 twin-disc shoulder | original geometry"
sketch "623ZZ outer race | profile (1)" plane through (0, 0, 2) normal (0, 0, 1) x (1, 0, 0) in component "11:1 twin-disc shoulder | original geometry"
  circle A0 centre (40, 0) radius 5
  circle A1 centre (40, 0) radius 4
extrude "623ZZ outer race (1)" add sketch "623ZZ outer race | profile (1)" along normal blind 4 separate body makes body 222 in component "11:1 twin-disc shoulder | original geometry"
ref_plane "WorkPlane19" through (0, 0, 2) normal (0, 0, 1) x (1, 0, 0) in component "11:1 twin-disc shoulder | original geometry"
sketch "623ZZ inner race | profile (1)" plane through (0, 0, 2) normal (0, 0, 1) x (1, 0, 0) in component "11:1 twin-disc shoulder | original geometry"
  circle A0 centre (40, 0) radius 2.5
  circle A1 centre (40, 0) radius 1.5
extrude "623ZZ inner race (1)" add sketch "623ZZ inner race | profile (1)" along normal blind 4 separate body makes body 223 in component "11:1 twin-disc shoulder | original geometry"
ref_plane "WorkPlane20" through (0, 0, 2.15) normal (0, 0, 1) x (1, 0, 0) in component "11:1 twin-disc shoulder | original geometry"
sketch "623ZZ shield | profile (1)" plane through (0, 0, 2.15) normal (0, 0, 1) x (1, 0, 0) in component "11:1 twin-disc shoulder | original geometry"
  circle A0 centre (40, 0) radius 4
  circle A1 centre (40, 0) radius 2.5
extrude "623ZZ shield (1)" add sketch "623ZZ shield | profile (1)" along normal blind 3.7 separate body makes body 224 in component "11:1 twin-disc shoulder | original geometry"
ref_plane "WorkPlane21" through (0, 0, -17) normal (0, 0, 1) x (1, 0, 0) in component "11:1 twin-disc shoulder | original geometry"
sketch "Fixed metal roller pin 2 | profile" plane through (0, 0, -17) normal (0, 0, 1) x (1, 0, 0) in component "11:1 twin-disc shoulder | original geometry"
  circle A0 centre (34.641, 20) radius 1.5
extrude "Fixed metal roller pin 2" add sketch "Fixed metal roller pin 2 | profile" along normal blind 34 separate body makes body 225 in component "11:1 twin-disc shoulder | original geometry"
ref_plane "WorkPlane22" through (0, 0, -6) normal (0, 0, 1) x (1, 0, 0) in component "11:1 twin-disc shoulder | original geometry"
sketch "623ZZ outer race | profile (2)" plane through (0, 0, -6) normal (0, 0, 1) x (1, 0, 0) in component "11:1 twin-disc shoulder | original geometry"
  circle A0 centre (34.641, 20) radius 5
  circle A1 centre (34.641, 20) radius 4
extrude "623ZZ outer race (2)" add sketch "623ZZ outer race | profile (2)" along normal blind 4 separate body makes body 226 in component "11:1 twin-disc shoulder | original geometry"
ref_plane "WorkPlane23" through (0, 0, -6) normal (0, 0, 1) x (1, 0, 0) in component "11:1 twin-disc shoulder | original geometry"
sketch "623ZZ inner race | profile (2)" plane through (0, 0, -6) normal (0, 0, 1) x (1, 0, 0) in component "11:1 twin-disc shoulder | original geometry"
  circle A0 centre (34.641, 20) radius 2.5
  circle A1 centre (34.641, 20) radius 1.5
extrude "623ZZ inner race (2)" add sketch "623ZZ inner race | profile (2)" along normal blind 4 separate body makes body 227 in component "11:1 twin-disc shoulder | original geometry"
ref_plane "WorkPlane24" through (0, 0, -5.85) normal (0, 0, 1) x (1, 0, 0) in component "11:1 twin-disc shoulder | original geometry"
sketch "623ZZ shield | profile (2)" plane through (0, 0, -5.85) normal (0, 0, 1) x (1, 0, 0) in component "11:1 twin-disc shoulder | original geometry"
  circle A0 centre (34.641, 20) radius 4
  circle A1 centre (34.641, 20) radius 2.5
extrude "623ZZ shield (2)" add sketch "623ZZ shield | profile (2)" along normal blind 3.7 separate body makes body 228 in component "11:1 twin-disc shoulder | original geometry"
ref_plane "WorkPlane25" through (0, 0, 2) normal (0, 0, 1) x (1, 0, 0) in component "11:1 twin-disc shoulder | original geometry"
sketch "623ZZ outer race | profile (3)" plane through (0, 0, 2) normal (0, 0, 1) x (1, 0, 0) in component "11:1 twin-disc shoulder | original geometry"
  circle A0 centre (34.641, 20) radius 5
  circle A1 centre (34.641, 20) radius 4
extrude "623ZZ outer race (3)" add sketch "623ZZ outer race | profile (3)" along normal blind 4 separate body makes body 229 in component "11:1 twin-disc shoulder | original geometry"
ref_plane "WorkPlane26" through (0, 0, 2) normal (0, 0, 1) x (1, 0, 0) in component "11:1 twin-disc shoulder | original geometry"
sketch "623ZZ inner race | profile (3)" plane through (0, 0, 2) normal (0, 0, 1) x (1, 0, 0) in component "11:1 twin-disc shoulder | original geometry"
  circle A0 centre (34.641, 20) radius 2.5
  circle A1 centre (34.641, 20) radius 1.5
extrude "623ZZ inner race (3)" add sketch "623ZZ inner race | profile (3)" along normal blind 4 separate body makes body 230 in component "11:1 twin-disc shoulder | original geometry"
ref_plane "WorkPlane27" through (0, 0, 2.15) normal (0, 0, 1) x (1, 0, 0) in component "11:1 twin-disc shoulder | original geometry"
sketch "623ZZ shield | profile (3)" plane through (0, 0, 2.15) normal (0, 0, 1) x (1, 0, 0) in component "11:1 twin-disc shoulder | original geometry"
  circle A0 centre (34.641, 20) radius 4
  circle A1 centre (34.641, 20) radius 2.5
extrude "623ZZ shield (3)" add sketch "623ZZ shield | profile (3)" along normal blind 3.7 separate body makes body 231 in component "11:1 twin-disc shoulder | original geometry"
ref_plane "WorkPlane28" through (0, 0, -17) normal (0, 0, 1) x (1, 0, 0) in component "11:1 twin-disc shoulder | original geometry"
sketch "Fixed metal roller pin 3 | profile" plane through (0, 0, -17) normal (0, 0, 1) x (1, 0, 0) in component "11:1 twin-disc shoulder | original geometry"
  circle A0 centre (20, 34.641) radius 1.5
extrude "Fixed metal roller pin 3" add sketch "Fixed metal roller pin 3 | profile" along normal blind 34 separate body makes body 232 in component "11:1 twin-disc shoulder | original geometry"
ref_plane "WorkPlane29" through (0, 0, -6) normal (0, 0, 1) x (1, 0, 0) in component "11:1 twin-disc shoulder | original geometry"
sketch "623ZZ outer race | profile (4)" plane through (0, 0, -6) normal (0, 0, 1) x (1, 0, 0) in component "11:1 twin-disc shoulder | original geometry"
  circle A0 centre (20, 34.641) radius 5
  circle A1 centre (20, 34.641) radius 4
extrude "623ZZ outer race (4)" add sketch "623ZZ outer race | profile (4)" along normal blind 4 separate body makes body 233 in component "11:1 twin-disc shoulder | original geometry"
ref_plane "WorkPlane30" through (0, 0, -6) normal (0, 0, 1) x (1, 0, 0) in component "11:1 twin-disc shoulder | original geometry"
sketch "623ZZ inner race | profile (4)" plane through (0, 0, -6) normal (0, 0, 1) x (1, 0, 0) in component "11:1 twin-disc shoulder | original geometry"
  circle A0 centre (20, 34.641) radius 2.5
  circle A1 centre (20, 34.641) radius 1.5
extrude "623ZZ inner race (4)" add sketch "623ZZ inner race | profile (4)" along normal blind 4 separate body makes body 234 in component "11:1 twin-disc shoulder | original geometry"
ref_plane "WorkPlane31" through (0, 0, -5.85) normal (0, 0, 1) x (1, 0, 0) in component "11:1 twin-disc shoulder | original geometry"
sketch "623ZZ shield | profile (4)" plane through (0, 0, -5.85) normal (0, 0, 1) x (1, 0, 0) in component "11:1 twin-disc shoulder | original geometry"
  circle A0 centre (20, 34.641) radius 4
  circle A1 centre (20, 34.641) radius 2.5
extrude "623ZZ shield (4)" add sketch "623ZZ shield | profile (4)" along normal blind 3.7 separate body makes body 235 in component "11:1 twin-disc shoulder | original geometry"
ref_plane "WorkPlane32" through (0, 0, 2) normal (0, 0, 1) x (1, 0, 0) in component "11:1 twin-disc shoulder | original geometry"
sketch "623ZZ outer race | profile (5)" plane through (0, 0, 2) normal (0, 0, 1) x (1, 0, 0) in component "11:1 twin-disc shoulder | original geometry"
  circle A0 centre (20, 34.641) radius 5
  circle A1 centre (20, 34.641) radius 4
extrude "623ZZ outer race (5)" add sketch "623ZZ outer race | profile (5)" along normal blind 4 separate body makes body 236 in component "11:1 twin-disc shoulder | original geometry"
ref_plane "WorkPlane33" through (0, 0, 2) normal (0, 0, 1) x (1, 0, 0) in component "11:1 twin-disc shoulder | original geometry"
sketch "623ZZ inner race | profile (5)" plane through (0, 0, 2) normal (0, 0, 1) x (1, 0, 0) in component "11:1 twin-disc shoulder | original geometry"
  circle A0 centre (20, 34.641) radius 2.5
  circle A1 centre (20, 34.641) radius 1.5
extrude "623ZZ inner race (5)" add sketch "623ZZ inner race | profile (5)" along normal blind 4 separate body makes body 237 in component "11:1 twin-disc shoulder | original geometry"
ref_plane "WorkPlane34" through (0, 0, 2.15) normal (0, 0, 1) x (1, 0, 0) in component "11:1 twin-disc shoulder | original geometry"
sketch "623ZZ shield | profile (5)" plane through (0, 0, 2.15) normal (0, 0, 1) x (1, 0, 0) in component "11:1 twin-disc shoulder | original geometry"
  circle A0 centre (20, 34.641) radius 4
  circle A1 centre (20, 34.641) radius 2.5
extrude "623ZZ shield (5)" add sketch "623ZZ shield | profile (5)" along normal blind 3.7 separate body makes body 238 in component "11:1 twin-disc shoulder | original geometry"
ref_plane "WorkPlane35" through (0, 0, -17) normal (0, 0, 1) x (1, 0, 0) in component "11:1 twin-disc shoulder | original geometry"